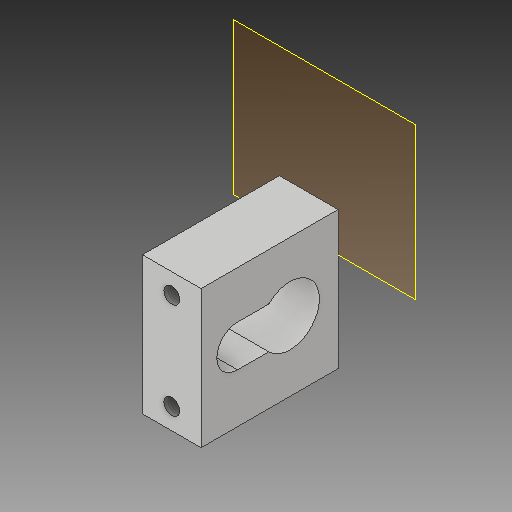
# Autodesk Inventor part: nucleo eje
Saved by Autodesk Inventor 2017 (Build 210142000, 142)
## iProperties
Part Number: nucleo eje
Material: Genérico
Document SubType Name: Modeling
Designer: HP Pav
Density: 1 g/cm^3
Appearance: Valor por defecto
Author: HP Pav
Autodesk Inventor part; units mm, degrees
ref_plane "YZ Plane" through (0, 0, 0) normal (1, 0, 0) x (0, 1, 0)
ref_plane "XZ Plane" through (0, 0, 0) normal (0, 1, 0) x (-1, 0, 0)
ref_plane "XY Plane" through (0, 0, 0) normal (0, 0, 1) x (1, 0, 0)
ref_plane "Plano de trabajo1" through (0, 0, 0) normal (0, 0, 1) x (1, 0, 0)
sketch "Boceto1" plane through (0, 0, 0) normal (0, 0, 1) x (1, 0, 0)
  line L0 (46.9045, -18.5) -> (-52.5955, -18.5) projected
  line L1 (-52.5955, -88.5) -> (46.9045, -88.5) projected
  line L2 (-22.8955, -18.5) -> (6.9045, -18.5)
  line L3 (6.9045, -18.5) -> (6.9045, -88.5)
  line L4 (6.9045, -88.5) -> (-22.8955, -88.5)
  line L5 (-22.8955, -88.5) -> (-22.8955, -18.5)
  line L6 (-52.5955, -18.5) -> (-52.5955, -88.5) projected
  line L7 (46.9045, -88.5) -> (46.9045, -18.5) projected
  point P0 (0, 0)
  dimension "d0" = 29.8
  dimension "d33" = 29.7
  constraints: 8 end point, 2 parallel, 2 point on line, 1 horizontal, 1 perpendicular
  measures "d0" distance between parallel lines of L3 L5
  measures "d33" distance between parallel lines of L6 L5
extrude "Extrusión1" add sketch "Boceto1" along normal blind 69.6 contours L3 L1 L5 L0
sketch "Boceto2" plane through (-22.8955, -88.5, 0) normal (-1, 0, 0) x (0, 0, 1)
  arc A0 (35.2121, 46) -> (35.2121, 25) centre (24.5, 35.5) ccw
  arc A1 (51.1, 25) -> (51.1, 46) centre (51.1, 35.5) ccw
  line L0 (51.1, 46) -> (35.2121, 46)
  line L1 (51.1, 25) -> (35.2121, 25)
  line L2 (9.5, 35.5) -> (9.5, 59.1781)
  line L3 (61.6, 35.5) -> (61.6, 59.1781)
  line L4 (24.5, 20.5) -> (11.6861, 20.5)
  line L5 (0, 0) -> (69.6, 0) projected
  line L6 (0, 70) -> (0, 0) projected
  line L7 (69.6, 70) -> (69.6, 0) projected
  point P0 (0, 88.5)
  dimension "d3" = 30
  dimension "d4" = 21
  dimension "d5" = 52.1
  dimension "d6" = 20.5
  dimension "d7" = 9.5
  constraints: 10 end point, 7 point on circle, 3 horizontal, 2 centre point, 2 tangent, 2 vertical
  measures "d3" diameter of A0
  measures "d4" diameter of A1
  measures "d5" distance between parallel lines of L2 L3
  measures "d6" distance between parallel lines of L5 L4
  measures "d7" distance between parallel lines of L6 L2
extrude "Extrusión2" cut sketch "Boceto2" against normal through all
hole "Agujero1" at (-7.9955, -28.8, 69.6) direction (0, 0, -1) diameter 8 depth 20 tip angle 118
hole "Agujero2" at (-7.9955, -77.8, 69.6) direction (0, 0, -1) diameter 8 depth 20 tip angle 118
thread "Rosca1" size "M8x1.25" class "6H" standard "ANSI Metric M Profile" full length
thread "Rosca2" size "M8x1.25" class "6H" standard "ANSI Metric M Profile" full length
